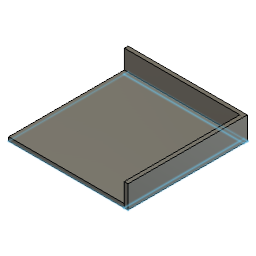
baseplate_corner_chess_V1 (Autodesk Fusion 360 design; units mm, degrees)
part number: 2026-04-16-14-42-29-878
Autodesk Fusion 360 part; units mm, degrees
sketch "Sketch3" plane through (0, 0, 0) normal (0, 1, 0) x (1, 0, 0)
  line L0 (15, -15) -> (167.4, -15)
  line L1 (167.4, -15) -> (167.4, -167.4)
  line L2 (167.4, -167.4) -> (15, -167.4)
  line L3 (15, -167.4) -> (15, -15)
  line L4 (15.0113, -10.0114) -> (172.4113, -10.0114)
  line L5 (172.4113, -10.0114) -> (172.4113, -15.0114)
  line L6 (172.4113, -15.0114) -> (15.0113, -15.0114)
  line L7 (15.0113, -15.0114) -> (15.0113, -10.0114)
  line L8 (167.4, -10.0114) -> (172.4, -10.0114)
  line L9 (172.4, -10.0114) -> (172.4, -167.4114)
  line L10 (172.4, -167.4114) -> (167.4, -167.4114)
  line L11 (167.4, -167.4114) -> (167.4, -10.0114)
  dimension "d8" = 152.4
  dimension "d9" = 152.4
  dimension "d10" = 157.4
  dimension "d11" = 5
  dimension "d12" = 5
  dimension "d13" = 157.4
  constraint horizontal L0
  constraint vertical L1
  constraint horizontal L2
  constraint vertical L3
  constraint horizontal L4
  constraint vertical L5
  constraint horizontal L6
  constraint vertical L7
  constraint horizontal L8
  constraint vertical L9
  constraint horizontal L10
  constraint vertical L11
  constraint coincident L4 L8.start
  measures "d8" distance of L0.start L0.end
  measures "d9" distance of L0.start L2.end
  measures "d10" distance of L4.start L4.end
  measures "d11" distance of L4.start L6.end
  measures "d12" distance of L8.start L8.end
  measures "d13" distance of L8.start L10.end
extrude "Extrude2" add sketch "Sketch3" along normal blind 30 contours L0 L4 L7 L11 makes body 1
extrude "Extrude3" add sketch "Sketch3" along normal blind 5 separate body contours L0 L1 L2 L3 L6 L7 L11 makes body 2
extrude "Extrude4" add sketch "Sketch3" along normal blind 30 contours L1 L6 L9 L10 L11 bodies 2
extrude "Extrude5" add sketch "Sketch3" along normal blind 30 contours L1 L4 L6 L8 L9 L11 bodies 1 2
extrude "Extrude6" cut 1 faces at (172.4, 10, 62.4781) along direction (-1, 0, 0) blind 2 on bodies 1 bodies 1
move_face "OffsetFaces1" offset -2 1 faces at (66.8075, 20, 10.0114) on bodies 1
extrude "Extrude7" cut 1 faces at (65.8038, 5, 116.6038) along direction (0, -1, 0) blind 2 on bodies 1 bodies 1
sketch "Sketch4" plane through (0, 0, 0) normal (0, 1, 0) x (1, 0, 0)
extrude "Extrude8" add 1 faces at (65.8038, 3, 116.6038) along direction (0, 1, 0) blind 2 on bodies 1 bodies 1
extrude "Extrude9" add 1 faces at (66.8075, 10, 12.0114) along direction (0, 0, -1) blind 2 on bodies 1 bodies 1
extrude "Extrude10" add 1 faces at (170.4, 10, 62.4781) along direction (1, 0, 0) blind 2 on bodies 1 bodies 1
extrude "Extrude11" add 1 faces at (119.9371, 10, 10.0114) along direction (0, 0, -1) blind 0.011 on bodies 1 bodies 1
sketch "Sketch5" plane through (0, 0, 0) normal (0, 1, 0) x (1, 0, 0)
